gripper-body (Autodesk Fusion 360 design; units mm, degrees)
Autodesk Fusion 360 part; units mm, degrees
sketch "스케치1" plane through (0, 0, 0) normal (0, 0, 1) x (1, 0, 0)
  line L0 (0, 0) -> (60, 0)
  line L1 (60, 0) -> (60, 60)
  line L2 (60, 60) -> (0, 60)
  line L3 (0, 60) -> (0, 0)
  line L4 (3, 3) -> (57, 3)
  line L5 (57, 3) -> (57, 57)
  line L6 (57, 57) -> (3, 57)
  line L7 (3, 57) -> (3, 3)
  dimension "d1" = 60
  dimension "d2" = 60
  dimension "d3" = 3
  dimension "d4" = 3
  dimension "d5" = 3
  dimension "d6" = 3
  constraint horizontal L0
  constraint vertical L1
  constraint horizontal L2
  constraint vertical L3
  constraint coincident L0.start L3.end
  constraint horizontal L4
  constraint vertical L5
  constraint horizontal L6
  constraint vertical L7
  measures "d1" distance of L0.start L0.end
  measures "d2" distance of L0.start L2.end
  measures "d3" distance of L0 L4
  measures "d4" distance of L1 L5
  measures "d5" distance of L2 L6
  measures "d6" distance of L3 L7
extrude "돌출1" add sketch "스케치1" along normal blind 50
extrude "돌출2" cut 1 faces at (3, 39, 33.3333) along direction (-1, 0, 0) blind 5
